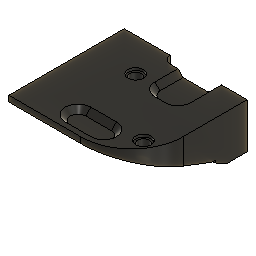
buffer_block_bottom (Autodesk Fusion 360 design; units mm, degrees)
part number: 2026-08-21-11-12-18-020
Autodesk Fusion 360 part; units mm, degrees
sketch "Sketch1" plane through (0, 0, 0) normal (0, 0, 1) x (1, 0, 0)
  line L0 (0, 0) -> (48, 0)
  line L1 (48, 0) -> (48, -47)
  line L2 (48, -47) -> (0, -47)
  line L3 (0, -47) -> (0, 0)
  dimension "d1" = 48
  dimension "d2" = 47
  constraint horizontal L0
  constraint vertical L1
  constraint horizontal L2
  constraint vertical L3
  constraint coincident L0.start L3.end
  measures "d1" distance of L0.start L0.end
  measures "d2" distance of L0.start L2.end
extrude "Extrude1" add sketch "Sketch1" along normal blind 14.175
sketch "Sketch2" plane through (48, 0, 0) normal (1, 0, 0) x (0, 1, 0)
  line L0 (-47, 0) -> (0, 0)
  line L1 (0, 0) -> (0, 14.175)
  line L2 (0, 14.175) -> (-47, 14.175)
  line L3 (-47, 14.175) -> (-47, 0)
  line L4 (-16, 0) -> (-47, 11.875)
  line L5 (-47, 0) -> (-47, 11.875)
  line L6 (-47, 0) -> (-16, 0)
  dimension "d5" = 31
  dimension "d6" = 11.875
  constraint coincident L0 L4.start
  constraint coincident L3 L4.end
  constraint coincident L0.start L3.end
  measures "d5" distance of L4.start L0.start
  measures "d6" distance of L4.end L0.start
extrude "Extrude2" cut sketch "Sketch2" against normal blind 100 contours L0 L3 L4 L5 L6
fillet "Fillet1" radius 20 1 edges at (48, -47, 13.025)
sketch "Sketch3" plane through (0, 0, 14.175) normal (0, 0, 1) x (-1, 0, 0)
  arc A0 (-28, 47) -> (-48, 27) centre (-28, 27) ccw
  line L0 (-48, 27) -> (-48, 0)
  line L1 (-48, 0) -> (0, 0)
  line L2 (0, 0) -> (0, 47)
  line L3 (0, 47) -> (-28, 47)
  circle A1 centre (-41.5154, 36.002) radius 2.25
  circle A2 centre (-17.5, 15) radius 2.25
  dimension "d11" = 4.5
  dimension "d12" = 4.5
  measures "d11" diameter of A1
  measures "d12" diameter of A2
extrude "Extrude3" cut sketch "Sketch3" against normal blind 20 contours A1 | A2
sketch "Sketch4" plane through (0, 0, 14.175) normal (0, 0, 1) x (-1, 0, 0)
  circle A0 centre (-17.5, 15) radius 2.25
  circle A1 centre (-41.5154, 36.002) radius 2.25
  arc A2 (-28, 47) -> (-48, 27) centre (-28, 27) ccw
  line L0 (-48, 27) -> (-48, 0)
  line L1 (-48, 0) -> (0, 0)
  line L2 (0, 0) -> (0, 47)
  line L3 (0, 47) -> (-28, 47)
  circle A3 centre (-17.5, 15) radius 3
  circle A4 centre (-41.5154, 36.002) radius 3
  dimension "d15" = 6
  dimension "d16" = 6
  constraint concentric A0 A3
  constraint concentric A1 A4
  measures "d15" diameter of A3
  measures "d16" diameter of A4
extrude "Extrude4" cut sketch "Sketch4" against normal blind 1 contours A3 | A4
sketch "Sketch5" plane through (0, 0, 0) normal (0, 0, -1) x (1, 0, 0)
  arc A0 (15.4844, 16) -> (19.5156, 16) centre (17.5, 15) ccw
  line L0 (15.4844, 16) -> (0, 16)
  line L1 (0, 16) -> (0, 0)
  line L2 (0, 0) -> (48, 0)
  line L3 (48, 0) -> (48, 16)
  line L4 (48, 16) -> (19.5156, 16)
  line L5 (38, 0) -> (18, 0)
  line L6 (18, 0) -> (18, 5)
  line L7 (18, 5) -> (38, 5)
  line L8 (38, 5) -> (38, 0)
  dimension "d19" = 10
  dimension "d20" = 30
  dimension "d21" = 5
  constraint horizontal L5
  constraint vertical L6
  constraint horizontal L7
  constraint vertical L8
  constraint coincident L2 L5.start
  measures "d19" distance of L3 L8
  measures "d20" distance of L3 L6
  measures "d21" distance of L5.start L7.end
extrude "Extrude5" cut sketch "Sketch5" against normal blind 100 contours L2 L5 L6 L7 L8
fillet "Fillet2" radius 3 2 edges at (38, -5, 7.0875) (18, -5, 7.0875)
sketch "Sketch6" plane through (0, 0, 14.175) normal (0, 0, 1) x (-1, 0, 0)
  line L0 (-38, 0) -> (-38, 2)
  arc A0 (-35, 5) -> (-38, 2) centre (-35, 2) ccw
  line L1 (-35, 5) -> (-21, 5)
  arc A1 (-18, 2) -> (-21, 5) centre (-21, 2) ccw
  line L2 (-18, 2) -> (-18, 0)
  line L3 (-18, 0) -> (0, 0)
  line L4 (0, 0) -> (0, 47)
  line L5 (0, 47) -> (-28, 47)
  arc A2 (-28, 47) -> (-48, 27) centre (-28, 27) ccw
  line L6 (-48, 27) -> (-48, 0)
  line L7 (-48, 0) -> (-38, 0)
  circle A3 centre (-17.5, 15) radius 3
  circle A4 centre (-41.5154, 36.002) radius 3
  line L8 (-15, 47) -> (-35, 47)
  line L9 (-35, 47) -> (-35, 35)
  line L10 (-35, 35) -> (-15, 35)
  line L11 (-15, 35) -> (-15, 47)
  line L12 (-15, 47) -> (-35, 47)
  line L13 (-35, 47) -> (-35, 45)
  line L14 (-35, 45) -> (-15, 45)
  line L15 (-15, 45) -> (-15, 47)
  dimension "d26" = 15
  dimension "d28" = 35
  dimension "d29" = 12
  dimension "d30" = 2
  constraint horizontal L8
  constraint vertical L9
  constraint horizontal L10
  constraint vertical L11
  constraint coincident L5 L8.start
  constraint horizontal L12
  constraint vertical L13
  constraint horizontal L14
  constraint vertical L15
  constraint coincident L9 L13.end
  measures "d26" distance of L4 L11
  measures "d28" distance of L4 L9
  measures "d29" distance of L5 L10
  measures "d30" distance of L12 L14
extrude "Extrude6" cut sketch "Sketch6" against normal blind 2 contours L9 L10 L11 L14
fillet "Fillet3" radius 5 4 edges at (15, -35, 13.175) (35, -35, 13.175) (15, -45, 13.175) (35, -45, 13.175)
sketch "Sketch7" plane through (0, 0, 14.175) normal (0, 0, 1) x (-1, 0, 0)
  arc A0 (-20, 35) -> (-20, 45) centre (-20, 40) ccw
  line L0 (-20, 35) -> (-30, 35)
  arc A1 (-30, 45) -> (-30, 35) centre (-30, 40) ccw
  line L1 (-30, 45) -> (-20, 45)
  line L2 (-38, 0) -> (-38, 2)
  arc A2 (-35, 5) -> (-38, 2) centre (-35, 2) ccw
  line L3 (-35, 5) -> (-21, 5)
  arc A3 (-18, 2) -> (-21, 5) centre (-21, 2) ccw
  line L4 (-18, 2) -> (-18, 0)
  line L5 (-18, 0) -> (0, 0)
  line L6 (0, 0) -> (0, 47)
  line L7 (0, 47) -> (-28, 47)
  arc A4 (-28, 47) -> (-48, 27) centre (-28, 27) ccw
  line L8 (-48, 27) -> (-48, 0)
  line L9 (-48, 0) -> (-38, 0)
  circle A5 centre (-17.5, 15) radius 3
  circle A6 centre (-41.5154, 36.002) radius 3
  line L10 (-38, 0.1124) -> (-24, 0.1124)
  line L11 (-24, 0.1124) -> (-24, 19)
  line L12 (-24, 19) -> (-38, 19)
  line L13 (-38, 19) -> (-38, 0.1124)
  constraint horizontal L10
  constraint vertical L11
  constraint horizontal L12
  constraint vertical L13
  constraint coincident L2 L10.start
extrude "Extrude7" cut sketch "Sketch7" against normal up to surface (2 mm away) contours A2 L3 L11 L12 L13
fillet "Fillet4" radius 5 2 edges at (24, -19, 13.175) (38, -19, 13.175)
sketch "Sketch8" plane through (0, 0, 0) normal (0, 0, -1) x (1, 0, 0)
  line L0 (38, 2) -> (38, 0)
  line L1 (38, 0) -> (48, 0)
  line L2 (48, 0) -> (48, 16)
  line L3 (48, 16) -> (19.5156, 16)
  arc A0 (15.4844, 16) -> (19.5156, 16) centre (17.5, 15) ccw
  line L4 (15.4844, 16) -> (0, 16)
  line L5 (0, 16) -> (0, 0)
  line L6 (0, 0) -> (18, 0)
  line L7 (18, 0) -> (18, 2)
  arc A1 (21, 5) -> (18, 2) centre (21, 2) ccw
  line L8 (21, 5) -> (35, 5)
  arc A2 (38, 2) -> (35, 5) centre (35, 2) ccw
  line L9 (48, 0) -> (0, 0)
  line L10 (0, 0) -> (0, 2)
  line L11 (0, 2) -> (48, 2)
  line L12 (48, 2) -> (48, 0)
  constraint horizontal L9
  constraint vertical L10
  constraint horizontal L11
  constraint vertical L12
  constraint coincident L5 L10.end
  constraint coincident L1.end L2.start
extrude "Extrude8" cut sketch "Sketch8" against normal blind 100 contours L0 L1 L2 L9 L11 L12 | L5 L6 L7 L9 L10 L11
sketch "Sketch10" plane through (48, 0, 0) normal (1, 0, 0) x (0, 1, 0)
  line L0 (-2, 0) -> (-2, 14.175)
  line L1 (-2, 14.175) -> (-27, 14.175)
  line L2 (-27, 14.175) -> (-27, 4.2137)
  line L3 (-27, 4.2137) -> (-16, 0)
  line L4 (-16, 0) -> (-2, 0)
  line L5 (-14.5, 0) -> (-2, 0)
  line L6 (-2, 0) -> (-2, -0.96)
  line L7 (-2, -0.96) -> (-14.5, -0.96)
  line L8 (-14.5, -0.96) -> (-14.5, 0)
  line L9 (-14.5, -0.96) -> (-4.9737, -6.46)
  line L10 (-4.9737, -6.46) -> (-2, -6.46)
  line L11 (-2, -6.46) -> (-2, -0.96)
  dimension "d41" = 1.5
  dimension "d42" = 30
  dimension "d43" = 11
  dimension "d50" = 0.96
  constraint horizontal L5
  constraint vertical L6
  constraint horizontal L7
  constraint vertical L8
  constraint coincident L4 L5.start
  constraint coincident L0 L6.end
  constraint horizontal L10
  constraint perpendicular L7 L11
  measures "d41" distance of L3.end L5.start
  measures "d42" angle of L7 L9
  measures "d43" distance of L7.end L9.end
  measures "d50" distance of L5 L7
extrude "Extrude9" add sketch "Sketch10" against normal up to surface (48 mm away) contours L4 L5 L6 L7 L8 | L7 L9 L10 L11
extrude "Extrude10" cut 1 faces at (18.155, -13.8161, 0) along direction (0, 0, -1) blind 100
extrude "Extrude11" cut 1 faces at (25.6667, -3, 0) along direction (0, 0, -1) up to surface (4.46 mm away)
chamfer "Chamfer1" distance 3 angle 45 1 edges at (48, -3.4869, -6.46) tangent chain off
chamfer "Chamfer2" distance 2 angle 45 4 edges at (25, -45, 12.175) (15, -40, 12.175) (25, -35, 12.175) (35, -40, 12.175) tangent chain off
chamfer "Chamfer3" distance 2 angle 45 5 edges at (36.5355, -17.5355, 12.175) (38, -8, 12.175) (24, -9.5, 12.175) (25.4645, -17.5355, 12.175) (31, -19, 12.175) tangent chain off
